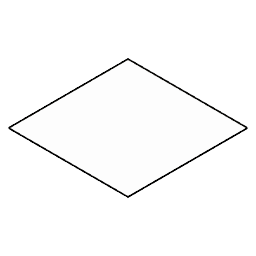
example1 (Autodesk Fusion 360 archive; units mm, degrees)
design "Patch cess v2 acyrlic"
Autodesk Fusion 360 part; units mm, degrees
sketch "Sketch1" plane through (0, 0, 0) normal (0, 0, 1) x (1, 0, 0)
  line L0 (-250, -250) -> (250, -250)
  line L1 (250, -250) -> (250, 250)
  line L2 (250, 250) -> (-250, 250)
  line L3 (-250, 250) -> (-250, -250)
  line L4 (-250, -250) -> (250, 250) construction
  line L5 (250, -250) -> (-250, 250) construction
  dimension "d1" = 500
  dimension "d2" = 500
  constraint horizontal L0
  constraint perpendicular L0 L1
  constraint parallel L0 L2
  constraint parallel L1 L3
  constraint coincident L4 origin
  constraint coincident L5 origin
  measures "d1" distance of L1.end L2.end
  measures "d2" distance of L0.end L1.end
extrude "Extrude1" add sketch "Sketch1" along normal blind 3

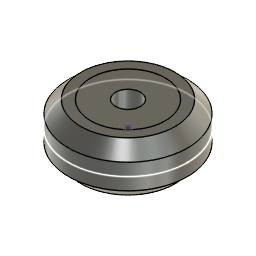
design "V Wheel"
Autodesk Fusion 360 part; units mm, degrees
sketch "Sketch1" plane through (0, 0, 0) normal (0, 0, 1) x (1, 0, 0)
  circle A0 centre (0, 0) radius 12
  dimension "d3" = 24
  constraint coincident A0.centre origin
  measures "d3" diameter of A0
sketch "Sketch3" plane through (0, 0, 0) normal (1, 0, 0) x (0, 1, 0)
  line L0 (12, 0) -> (-12, 0)
  line L1 (12, 0) -> (12, -2.5)
  line L2 (0, -5) -> (9.5, -5)
  line L3 (9.5, -5) -> (12, -2.5)
  line L4 (2.5, -5) -> (2.5, 0)
  line L5 (9.5, 5) -> (12, 2.5)
  line L6 (12, 0) -> (12, 2.5)
  line L7 (0, 5) -> (9.5, 5)
  line L8 (2.5, 5) -> (2.5, 0)
  dimension "d4" = 2.5
  dimension "d5" = 5
  dimension "d6" = 12
  dimension "d7" = 2.5
  dimension "d8" = 2.5
  constraint coincident L0 L1.start
  constraint perpendicular L0 L1
  constraint horizontal L2
  constraint coincident L2 L4.start
  constraint coincident L0 L4.end
  constraint perpendicular L0 L4
  constraint symmetric L0 L1.start L6.start
  constraint symmetric L0 L1.end L5.end
  constraint symmetric L0 L2.start L7.start
  constraint symmetric L0 L2.end L5.start
  constraint symmetric L0 L4.start L8.start
  constraint symmetric L0 L4.end L8.end
  measures "d4" distance of L0.start L1.end
  measures "d5" distance of L0 L2
  measures "d6" distance of L1 origin
  measures "d7" distance of L1 L2.end
  measures "d8" distance of origin L4
revolve "Revolve1" add sketch "Sketch3" angle 360 about axis through (0, 0, 1.75) along (0, 0, 1) makes body 1
sketch "Sketch4" plane through (0, 0, 5) normal (0, 0, 1) x (-1, 0, 0)
  circle A0 centre (0, 0) radius 2.5
  circle A1 centre (0, 0) radius 9.5
  circle A2 centre (0, 0) radius 7.5
  dimension "d10" = 15
  constraint coincident A0.centre A1.centre
  measures "d10" diameter of A2
split "Split1" by curves path "Sketch4" along A2 bodies 1 makes body 2 at (1.1118, 11.1112, -3.3333)

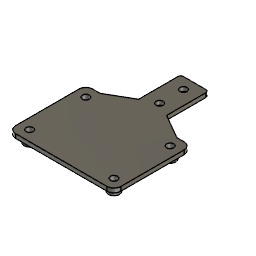
design "XY Bracket Chess Robot V2 Top"
Autodesk Fusion 360 part; units mm, degrees
sketch "Sketch1" plane through (0, 0, 0) normal (0, 0, 1) x (1, 0, 0)
  line L0 (30, 20) -> (-30, 20)
  line L1 (-30, 20) -> (-30, -20)
  line L2 (-30, -20) -> (30, -20)
  line L3 (30, -20) -> (30, 20)
  line L4 (30, 20) -> (-30, -20) construction
  line L5 (-30, 20) -> (30, -20) construction
  circle A0 centre (-30, 20) radius 2.5
  circle A1 centre (30, 20) radius 2.5
  circle A2 centre (30, -20) radius 2.5
  circle A3 centre (-30, -20) radius 2.5
  line L6 (32.5, 27.5) -> (-32.5, 27.5)
  line L7 (-37.5, 22.5) -> (-37.5, -22.5)
  line L8 (-32.5, -27.5) -> (32.5, -27.5)
  line L9 (37.5, -22.5) -> (37.5, 22.5)
  line L10 (37.5, 27.5) -> (-37.5, -27.5) construction
  line L11 (-37.5, 27.5) -> (37.5, -27.5) construction
  arc A4 (-32.5, 27.5) -> (-37.5, 22.5) centre (-32.5, 22.5) ccw
  arc A5 (37.5, 22.5) -> (32.5, 27.5) centre (32.5, 22.5) ccw
  arc A6 (32.5, -27.5) -> (37.5, -22.5) centre (32.5, -22.5) ccw
  arc A7 (-37.5, -22.5) -> (-32.5, -27.5) centre (-32.5, -22.5) ccw
  line L12 (-10, 27.5) -> (10, 27.5)
  line L13 (10, 27.5) -> (10, 65.5)
  line L14 (8, 67.5) -> (-8, 67.5)
  line L15 (-10, 65.5) -> (-10, 27.5)
  line L16 (-10, 37.5) -> (-27.3205, 27.5)
  line L17 (10, 37.5) -> (27.3205, 27.5)
  arc A8 (-8, 67.5) -> (-10, 65.5) centre (-8, 65.5) ccw
  arc A9 (10, 65.5) -> (8, 67.5) centre (8, 65.5) ccw
  circle A10 centre (0, 59.5) radius 2.5
  circle A11 centre (0, 42.5) radius 2.5
  point P0 (-10, 67.5)
  dimension "d1" = 60
  dimension "d2" = 40
  dimension "d3" = 5
  dimension "d4" = 5
  dimension "d5" = 5
  dimension "d6" = 5
  dimension "d7" = 75
  dimension "d8" = 55
  dimension "d9" = 5
  dimension "d10" = 5
  dimension "d11" = 5
  dimension "d12" = 5
  dimension "d13" = 20
  dimension "d14" = 40
  dimension "d15" = 10
  dimension "d17" = 30
  dimension "d19" = 2
  dimension "d20" = 2
  dimension "d21" = 5
  dimension "d22" = 5
  dimension "d23" = 8
  dimension "d24" = 25
  dimension "d27" = 20
  dimension "d28" = 20
  constraint horizontal L0
  constraint perpendicular L0 L1
  constraint parallel L0 L2
  constraint parallel L1 L3
  constraint coincident L4 origin
  constraint coincident L5 origin
  constraint coincident L0.end L1.start
  constraint coincident L0.start L3.end
  constraint coincident L2.end L3.start
  constraint coincident L1.end L2.start
  constraint horizontal L6
  constraint perpendicular L6 L7
  constraint parallel L6 L8
  constraint parallel L7 L9
  constraint coincident L10 origin
  constraint coincident L11 origin
  constraint coincident L11.start L7
  constraint coincident L11.start L6
  constraint tangent L7 A4
  constraint tangent L6 A4
  constraint coincident L10.start L6
  constraint coincident L10.start L9
  constraint tangent L6 A5
  constraint tangent L9 A5
  constraint coincident L11.end L9
  constraint coincident L11.end L8
  constraint tangent L9 A6
  constraint tangent L8 A6
  constraint coincident L10.end L7
  constraint coincident L10.end L8
  constraint tangent L7 A7
  constraint tangent L8 A7
  constraint horizontal L12
  constraint vertical L13
  constraint horizontal L14
  constraint vertical L15
  constraint coincident L6 L12.start
  constraint coincident L15 L16.start
  constraint coincident L6 L16.end
  constraint coincident L13 L17.start
  constraint coincident L6 L17.end
  constraint coincident P0 L15
  constraint coincident P0 L14
  constraint tangent L15 A8
  constraint tangent L14 A8
  constraint tangent L14 A9
  constraint tangent L13 A9
  constraint horizontal L16.start L17.start
  constraint vertical A10.centre A11.centre
  constraint vertical origin A11.centre
  measures "d1" distance of L1.end L2.end
  measures "d2" distance of L0.end L1.end
  measures "d3" diameter of A0
  measures "d4" diameter of A1
  measures "d5" diameter of A2
  measures "d6" diameter of A3
  measures "d7" distance of L10.end L11.end
  measures "d8" distance of L11.start L10.end
  measures "d9" radius of A4
  measures "d10" radius of A5
  measures "d11" radius of A6
  measures "d12" radius of A7
  measures "d13" distance of L12.start L12.end
  measures "d14" distance of L12.start P0
  measures "d15" distance of origin L13
  measures "d17" distance of L14 L16.start
  measures "d19" radius of A8
  measures "d20" radius of A9
  measures "d21" diameter of A10
  measures "d22" diameter of A11
  measures "d23" distance of L14 A10.centre
  measures "d24" distance of L14 A11.centre
  measures "d27" distance of L16.start L16.end
  measures "d28" distance of L17.start L17.end
extrude "Extrude1" add sketch "Sketch1" along normal blind 3 contours L0 L1 L2 L3 A0 A1 A2 A3 | L6 L7 L8 L9 A4 A5 A6 A7 L12 | L6 L13 L17 | L6 L12 L13 L14 L15 A8 A9 | L6 L15 L16
sketch "Sketch2" plane through (0, 0, 0) normal (0, 0, -1) x (1, 0, 0)
  circle A0 centre (30, 20) radius 2.5
  circle A1 centre (-30, -20) radius 2.5
  circle A2 centre (30, -20) radius 2.5
  circle A3 centre (0, -42.5) radius 2.5
  circle A4 centre (0, -59.5) radius 2.5
  circle A5 centre (-30, 20) radius 2.5
  line L0 (10, -65.5) -> (10, -37.5)
  line L1 (10, -37.5) -> (27.3205, -27.5)
  line L2 (27.3205, -27.5) -> (32.5, -27.5)
  arc A6 (32.5, -27.5) -> (37.5, -22.5) centre (32.5, -22.5) ccw
  line L3 (37.5, -22.5) -> (37.5, 22.5)
  arc A7 (37.5, 22.5) -> (32.5, 27.5) centre (32.5, 22.5) ccw
  line L4 (32.5, 27.5) -> (-32.5, 27.5)
  arc A8 (-32.5, 27.5) -> (-37.5, 22.5) centre (-32.5, 22.5) ccw
  line L5 (-37.5, 22.5) -> (-37.5, -22.5)
  arc A9 (-37.5, -22.5) -> (-32.5, -27.5) centre (-32.5, -22.5) ccw
  line L6 (-32.5, -27.5) -> (-27.3205, -27.5)
  line L7 (-27.3205, -27.5) -> (-10, -37.5)
  line L8 (-10, -37.5) -> (-10, -65.5)
  arc A10 (-10, -65.5) -> (-8, -67.5) centre (-8, -65.5) ccw
  line L9 (-8, -67.5) -> (8, -67.5)
  arc A11 (8, -67.5) -> (10, -65.5) centre (8, -65.5) ccw
  line L10 (10, -67.5) -> (-10, -67.5)
  line L11 (-10, -67.5) -> (-10, -27.5)
  line L12 (-10, -27.5) -> (10, -27.5)
  line L13 (10, -27.5) -> (10, -67.5)
  line L14 (-13, -70.5) -> (-13, -24.5)
  line L15 (-13, -24.5) -> (13, -24.5)
  line L16 (13, -24.5) -> (13, -70.5)
  line L17 (13, -70.5) -> (-13, -70.5)
  dimension "d29" = 40
  dimension "d30" = -3
  constraint horizontal L10
  constraint vertical L11
  constraint horizontal L12
  constraint vertical L13
  measures "d29" distance of L10.start L12.end
sketch "Sketch3" plane through (0, 0, 0) normal (0, 0, -1) x (1, 0, 0)
  circle A0 centre (30, 20) radius 2.5
  circle A1 centre (-30, -20) radius 2.5
  circle A2 centre (30, -20) radius 2.5
  circle A3 centre (0, -42.5) radius 2.5
  circle A4 centre (0, -59.5) radius 2.5
  circle A5 centre (-30, 20) radius 2.5
  line L0 (10, -65.5) -> (10, -37.5)
  line L1 (10, -37.5) -> (27.3205, -27.5)
  line L2 (27.3205, -27.5) -> (32.5, -27.5)
  arc A6 (32.5, -27.5) -> (37.5, -22.5) centre (32.5, -22.5) ccw
  line L3 (37.5, -22.5) -> (37.5, 22.5)
  arc A7 (37.5, 22.5) -> (32.5, 27.5) centre (32.5, 22.5) ccw
  line L4 (32.5, 27.5) -> (-32.5, 27.5)
  arc A8 (-32.5, 27.5) -> (-37.5, 22.5) centre (-32.5, 22.5) ccw
  line L5 (-37.5, 22.5) -> (-37.5, -22.5)
  arc A9 (-37.5, -22.5) -> (-32.5, -27.5) centre (-32.5, -22.5) ccw
  line L6 (-32.5, -27.5) -> (-27.3205, -27.5)
  line L7 (-27.3205, -27.5) -> (-10, -37.5)
  line L8 (-10, -37.5) -> (-10, -65.5)
  arc A10 (-10, -65.5) -> (-8, -67.5) centre (-8, -65.5) ccw
  line L9 (-8, -67.5) -> (8, -67.5)
  arc A11 (8, -67.5) -> (10, -65.5) centre (8, -65.5) ccw
  circle A12 centre (30, -20) radius 2.5
  circle A13 centre (30, -20) radius 4
  circle A14 centre (-30, -20) radius 2.5
  circle A15 centre (-30, -20) radius 4
  circle A16 centre (-30, 20) radius 2.5
  circle A17 centre (-30, 20) radius 4
  circle A18 centre (30, 20) radius 2.5
  circle A19 centre (30, 20) radius 4
  point P0 (-32.5, 20)
  dimension "d33" = 8
  dimension "d34" = 8
  dimension "d35" = 8
  dimension "d36" = 8
  constraint concentric A2 A12
  constraint concentric A12 A13
  constraint concentric A1 A14
  constraint concentric A14 A15
  constraint concentric A5 A16
  constraint coincident A16 P0
  constraint concentric A5 A17
  constraint concentric A0 A18
  constraint concentric A0 A19
  measures "d33" diameter of A13
  measures "d34" diameter of A15
  measures "d35" diameter of A17
  measures "d36" diameter of A19
extrude "Extrude3" add sketch "Sketch3" along normal blind 5 contours A13 | A15 | A17 | A19
extrude "Extrude2" [rolled back] along distance 20 taper angle 0

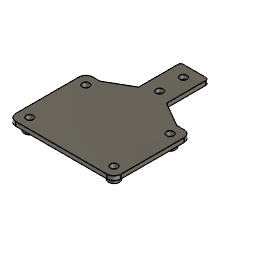
design "XY Bracket Chess Robot V2"
Autodesk Fusion 360 part; units mm, degrees
sketch "Sketch1" plane through (0, 0, 0) normal (0, 0, 1) x (1, 0, 0)
  line L0 (30, 20) -> (-30, 20)
  line L1 (-30, 20) -> (-30, -20)
  line L2 (-30, -20) -> (30, -20)
  line L3 (30, -20) -> (30, 20)
  line L4 (30, 20) -> (-30, -20) construction
  line L5 (-30, 20) -> (30, -20) construction
  circle A0 centre (-30, 20) radius 2.5
  circle A1 centre (30, 20) radius 2.5
  circle A2 centre (30, -20) radius 2.5
  circle A3 centre (-30, -20) radius 2.5
  line L6 (32.5, 27.5) -> (-32.5, 27.5)
  line L7 (-37.5, 22.5) -> (-37.5, -22.5)
  line L8 (-32.5, -27.5) -> (32.5, -27.5)
  line L9 (37.5, -22.5) -> (37.5, 22.5)
  line L10 (37.5, 27.5) -> (-37.5, -27.5) construction
  line L11 (-37.5, 27.5) -> (37.5, -27.5) construction
  arc A4 (-32.5, 27.5) -> (-37.5, 22.5) centre (-32.5, 22.5) ccw
  arc A5 (37.5, 22.5) -> (32.5, 27.5) centre (32.5, 22.5) ccw
  arc A6 (32.5, -27.5) -> (37.5, -22.5) centre (32.5, -22.5) ccw
  arc A7 (-37.5, -22.5) -> (-32.5, -27.5) centre (-32.5, -22.5) ccw
  line L12 (-10, 27.5) -> (10, 27.5)
  line L13 (10, 27.5) -> (10, 65.5)
  line L14 (8, 67.5) -> (-8, 67.5)
  line L15 (-10, 65.5) -> (-10, 27.5)
  line L16 (-10, 37.5) -> (-27.3205, 27.5)
  line L17 (10, 37.5) -> (27.3205, 27.5)
  arc A8 (-8, 67.5) -> (-10, 65.5) centre (-8, 65.5) ccw
  arc A9 (10, 65.5) -> (8, 67.5) centre (8, 65.5) ccw
  circle A10 centre (0, 59.5) radius 2.5
  circle A11 centre (0, 42.5) radius 2.5
  point P0 (-10, 67.5)
  dimension "d1" = 60
  dimension "d2" = 40
  dimension "d3" = 5
  dimension "d4" = 5
  dimension "d5" = 5
  dimension "d6" = 5
  dimension "d7" = 75
  dimension "d8" = 55
  dimension "d9" = 5
  dimension "d10" = 5
  dimension "d11" = 5
  dimension "d12" = 5
  dimension "d13" = 20
  dimension "d14" = 40
  dimension "d15" = 10
  dimension "d17" = 30
  dimension "d19" = 2
  dimension "d20" = 2
  dimension "d21" = 5
  dimension "d22" = 5
  dimension "d23" = 8
  dimension "d24" = 25
  dimension "d27" = 20
  dimension "d28" = 20
  constraint horizontal L0
  constraint perpendicular L0 L1
  constraint parallel L0 L2
  constraint parallel L1 L3
  constraint coincident L4 origin
  constraint coincident L5 origin
  constraint coincident L0.end L1.start
  constraint coincident L0.start L3.end
  constraint coincident L2.end L3.start
  constraint coincident L1.end L2.start
  constraint horizontal L6
  constraint perpendicular L6 L7
  constraint parallel L6 L8
  constraint parallel L7 L9
  constraint coincident L10 origin
  constraint coincident L11 origin
  constraint coincident L11.start L7
  constraint coincident L11.start L6
  constraint tangent L7 A4
  constraint tangent L6 A4
  constraint coincident L10.start L6
  constraint coincident L10.start L9
  constraint tangent L6 A5
  constraint tangent L9 A5
  constraint coincident L11.end L9
  constraint coincident L11.end L8
  constraint tangent L9 A6
  constraint tangent L8 A6
  constraint coincident L10.end L7
  constraint coincident L10.end L8
  constraint tangent L7 A7
  constraint tangent L8 A7
  constraint horizontal L12
  constraint vertical L13
  constraint horizontal L14
  constraint vertical L15
  constraint coincident L6 L12.start
  constraint coincident L15 L16.start
  constraint coincident L6 L16.end
  constraint coincident L13 L17.start
  constraint coincident L6 L17.end
  constraint coincident P0 L15
  constraint coincident P0 L14
  constraint tangent L15 A8
  constraint tangent L14 A8
  constraint tangent L14 A9
  constraint tangent L13 A9
  constraint horizontal L16.start L17.start
  constraint vertical A10.centre A11.centre
  constraint vertical origin A11.centre
  measures "d1" distance of L1.end L2.end
  measures "d2" distance of L0.end L1.end
  measures "d3" diameter of A0
  measures "d4" diameter of A1
  measures "d5" diameter of A2
  measures "d6" diameter of A3
  measures "d7" distance of L10.end L11.end
  measures "d8" distance of L11.start L10.end
  measures "d9" radius of A4
  measures "d10" radius of A5
  measures "d11" radius of A6
  measures "d12" radius of A7
  measures "d13" distance of L12.start L12.end
  measures "d14" distance of L12.start P0
  measures "d15" distance of origin L13
  measures "d17" distance of L14 L16.start
  measures "d19" radius of A8
  measures "d20" radius of A9
  measures "d21" diameter of A10
  measures "d22" diameter of A11
  measures "d23" distance of L14 A10.centre
  measures "d24" distance of L14 A11.centre
  measures "d27" distance of L16.start L16.end
  measures "d28" distance of L17.start L17.end
extrude "Extrude1" add sketch "Sketch1" along normal blind 3 contours L0 L1 L2 L3 A0 A1 A2 A3 | L6 L7 L8 L9 A4 A5 A6 A7 L12 | L6 L13 L17 | L6 L12 L13 L14 L15 A8 A9 | L6 L15 L16
sketch "Sketch2" plane through (0, 0, 0) normal (0, 0, -1) x (1, 0, 0)
  circle A0 centre (30, 20) radius 2.5
  circle A1 centre (-30, -20) radius 2.5
  circle A2 centre (30, -20) radius 2.5
  circle A3 centre (0, -42.5) radius 2.5
  circle A4 centre (0, -59.5) radius 2.5
  circle A5 centre (-30, 20) radius 2.5
  line L0 (10, -65.5) -> (10, -37.5)
  line L1 (10, -37.5) -> (27.3205, -27.5)
  line L2 (27.3205, -27.5) -> (32.5, -27.5)
  arc A6 (32.5, -27.5) -> (37.5, -22.5) centre (32.5, -22.5) ccw
  line L3 (37.5, -22.5) -> (37.5, 22.5)
  arc A7 (37.5, 22.5) -> (32.5, 27.5) centre (32.5, 22.5) ccw
  line L4 (32.5, 27.5) -> (-32.5, 27.5)
  arc A8 (-32.5, 27.5) -> (-37.5, 22.5) centre (-32.5, 22.5) ccw
  line L5 (-37.5, 22.5) -> (-37.5, -22.5)
  arc A9 (-37.5, -22.5) -> (-32.5, -27.5) centre (-32.5, -22.5) ccw
  line L6 (-32.5, -27.5) -> (-27.3205, -27.5)
  line L7 (-27.3205, -27.5) -> (-10, -37.5)
  line L8 (-10, -37.5) -> (-10, -65.5)
  arc A10 (-10, -65.5) -> (-8, -67.5) centre (-8, -65.5) ccw
  line L9 (-8, -67.5) -> (8, -67.5)
  arc A11 (8, -67.5) -> (10, -65.5) centre (8, -65.5) ccw
  line L10 (10, -67.5) -> (-10, -67.5)
  line L11 (-10, -67.5) -> (-10, -27.5)
  line L12 (-10, -27.5) -> (10, -27.5)
  line L13 (10, -27.5) -> (10, -67.5)
  line L14 (-13, -70.5) -> (-13, -24.5)
  line L15 (-13, -24.5) -> (13, -24.5)
  line L16 (13, -24.5) -> (13, -70.5)
  line L17 (13, -70.5) -> (-13, -70.5)
  dimension "d29" = 40
  dimension "d30" = -3
  constraint horizontal L10
  constraint vertical L11
  constraint horizontal L12
  constraint vertical L13
  measures "d29" distance of L10.start L12.end
extrude "Extrude2" add sketch "Sketch2" along normal blind 20 contours L1 L7 L11 L12 L13 L14 L15 L16
sketch "Sketch3" plane through (0, 24.5, 0) normal (0, -1, 0) x (1, 0, 0)
  line L0 (13, 0) -> (-13, 0)
  line L1 (-13, 0) -> (-13, -20)
  line L2 (-13, -20) -> (13, -20)
  line L3 (13, -20) -> (13, 0)
  line L4 (13, -20) -> (-13, 0) construction
  line L5 (13, 0) -> (-13, -20) construction
  circle A0 centre (0, -10) radius 2.5
  dimension "d33" = 5
  constraint coincident L2.end L3.start
  constraint coincident L0.end L1.start
  constraint coincident L0.start L3.end
  constraint coincident L1.end L2.start
  constraint midpoint L5 A0.centre
  measures "d33" diameter of A0
extrude "Extrude3" cut sketch "Sketch3" against normal blind 10 contours A0
fillet "Fillet1" radius 4 2 edges at (-13, 24.5, -10) (13, 24.5, -10)
sketch "Sketch4" plane through (0, 0, 0) normal (0, 0, -1) x (1, 0, 0)
  line L0 (13, -28.5) -> (13, -35.7679)
  line L1 (13, -35.7679) -> (27.3205, -27.5)
  line L2 (27.3205, -27.5) -> (32.5, -27.5)
  arc A0 (32.5, -27.5) -> (37.5, -22.5) centre (32.5, -22.5) ccw
  line L3 (37.5, -22.5) -> (37.5, 22.5)
  arc A1 (37.5, 22.5) -> (32.5, 27.5) centre (32.5, 22.5) ccw
  line L4 (32.5, 27.5) -> (-32.5, 27.5)
  arc A2 (-32.5, 27.5) -> (-37.5, 22.5) centre (-32.5, 22.5) ccw
  line L5 (-37.5, 22.5) -> (-37.5, -22.5)
  arc A3 (-37.5, -22.5) -> (-32.5, -27.5) centre (-32.5, -22.5) ccw
  line L6 (-32.5, -27.5) -> (-27.3205, -27.5)
  line L7 (-27.3205, -27.5) -> (-13, -35.7679)
  line L8 (-13, -35.7679) -> (-13, -28.5)
  arc A4 (-9, -24.5) -> (-13, -28.5) centre (-9, -28.5) ccw
  line L9 (-9, -24.5) -> (9, -24.5)
  arc A5 (13, -28.5) -> (9, -24.5) centre (9, -28.5) ccw
  circle A6 centre (30, 20) radius 2.5
  circle A7 centre (-30, -20) radius 2.5
  circle A8 centre (30, -20) radius 2.5
  circle A9 centre (-30, 20) radius 2.5
  circle A10 centre (30, -20) radius 4
  circle A11 centre (30, 20) radius 4
  circle A12 centre (30, 20) radius 2.5
  circle A13 centre (30, -20) radius 2.5
  circle A14 centre (-30, -20) radius 2.5
  circle A15 centre (-30, -20) radius 4
  circle A16 centre (-30, 20) radius 2.5
  circle A17 centre (-30, 20) radius 4
  point P0 (27.5, 20)
  point P1 (27.5, -20)
  point P2 (-32.5, -20)
  dimension "d38" = 8
  dimension "d39" = 8
  dimension "d40" = 8
  constraint concentric A8 A10
  constraint concentric A6 A11
  constraint concentric A11 A12
  constraint coincident A12 P0
  constraint concentric A8 A13
  constraint coincident A13 P1
  constraint concentric A7 A14
  constraint coincident A14 P2
  constraint concentric A14 A15
  constraint concentric A9 A16
  constraint concentric A16 A17
  measures "d38" diameter of A11
  measures "d39" diameter of A15
  measures "d40" diameter of A17
extrude "Extrude4" add sketch "Sketch4" along normal blind 5 contours A10 | A11 | A15 | A17
